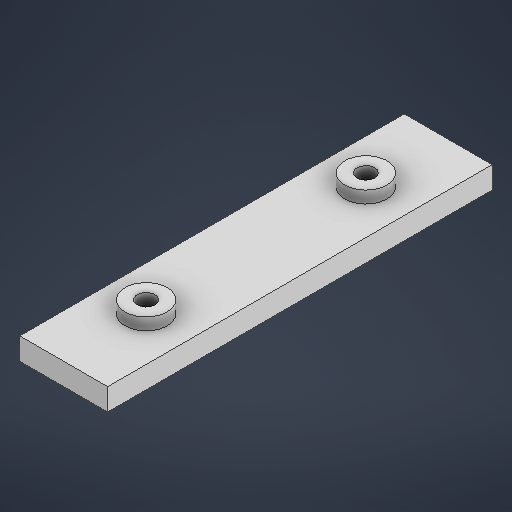
# Autodesk Inventor part: screw_lift
Saved by Autodesk Inventor 2027 (Build 310192060, 192F)
## iProperties
Created: 2026-09-17
Part Number: screw_lift
Material: Generic
Document SubType Name: Modeling
Designer: Aiden
Density: 1 g/cm^3
Appearance: Default
Author: Aiden
Autodesk Inventor part; units mm, degrees
ref_plane "YZ Plane" through (0, 0, 0) normal (1, 0, 0) x (0, 1, 0)
ref_plane "XZ Plane" through (0, 0, 0) normal (0, 1, 0) x (-1, 0, 0)
ref_plane "XY Plane" through (0, 0, 0) normal (0, 0, 1) x (1, 0, 0)
sketch "Sketch1" plane through (0, 0, 0) normal (0, 1, 0) x (-1, 0, 0)
  line L0 (0, 0) -> (8.128, 0)
  line L1 (8.128, 0) -> (8.128, -35.56)
  line L2 (8.128, -35.56) -> (0, -35.56)
  line L3 (0, -35.56) -> (0, 0)
  dimension "d0" = 35.56
  dimension "d1" = 8.128
  constraints: 8 end point, 2 parallel, 1 horizontal, 1 perpendicular
  measures "d0" distance between parallel lines of L2 L0
  measures "d1" distance of L1.end L2.end
extrude "Extrusion1" add sketch "Sketch1" along normal blind 2.032
sketch "Sketch2" plane through (0, 2.032, 0) normal (0, 1, 0) x (1, 0, 0)
  line L0 (-8.128, 5.08) -> (0, 5.08)
  line L1 (0, 5.08) -> (0, 10.16)
  line L2 (0, 10.16) -> (-8.128, 10.16)
  line L3 (-8.128, 10.16) -> (-8.128, 5.08)
  line L4 (-8.128, 25.4) -> (0, 25.4)
  line L5 (0, 25.4) -> (0, 30.48)
  line L6 (0, 30.48) -> (-8.128, 30.48)
  line L7 (-8.128, 30.48) -> (-8.128, 25.4)
  line L8 (0, 0) -> (0, 35.56) projected
  line L9 (-8.128, 35.56) -> (-8.128, 0) projected
  line L10 (-8.128, 0) -> (0, 0) projected
  line L11 (0, 35.56) -> (-8.128, 35.56) projected
  line L12 (0, 7.62) -> (-8.128, 7.62) construction
  line L13 (-4.064, 5.08) -> (-4.064, 10.16) construction
  line L14 (-4.064, 25.4) -> (-4.064, 30.48) construction
  line L15 (-8.128, 27.94) -> (0, 27.94) construction
  circle A0 centre (-4.064, 7.62) radius 1.95
  circle A1 centre (-4.064, 27.94) radius 1.95
  circle A2 centre (-4.064, 7.62) radius 0.825
  circle A3 centre (-4.064, 27.94) radius 0.825
  dimension "d4" = 5.08
  dimension "d5" = 5.08
  dimension "d6" = 5.08
  dimension "d7" = 3.9
  dimension "d10" = 1.65
  constraints: 24 end point, 8 point on line, 6 midpoint, 5 equal length, 4 centre point, 4 perpendicular, 2 coincident, 2 equal radius, 2 horizontal, 1 collinear
  measures "d4" distance of L2.end L0.start
  measures "d5" distance between parallel lines of L10 L0
  measures "d6" distance from line of L14.end L11
  measures "d7" diameter of A0
  measures "d10" diameter of A2
extrude "Extrusion2" add sketch "Sketch2" along normal blind 1.1176 contours A0 | A1
sketch "Sketch4" plane through (-4.064, 2.032, -7.62) normal (0, 1, 0) x (1, 0, 0)
  circle A0 centre (0, 0) radius 0.825 projected
  circle A1 centre (0, 20.32) radius 0.825 projected
  point P0 (4.064, -7.62)
extrude "Extrusion3" cut sketch "Sketch4" against normal blind 2.032
body "Solid1"
